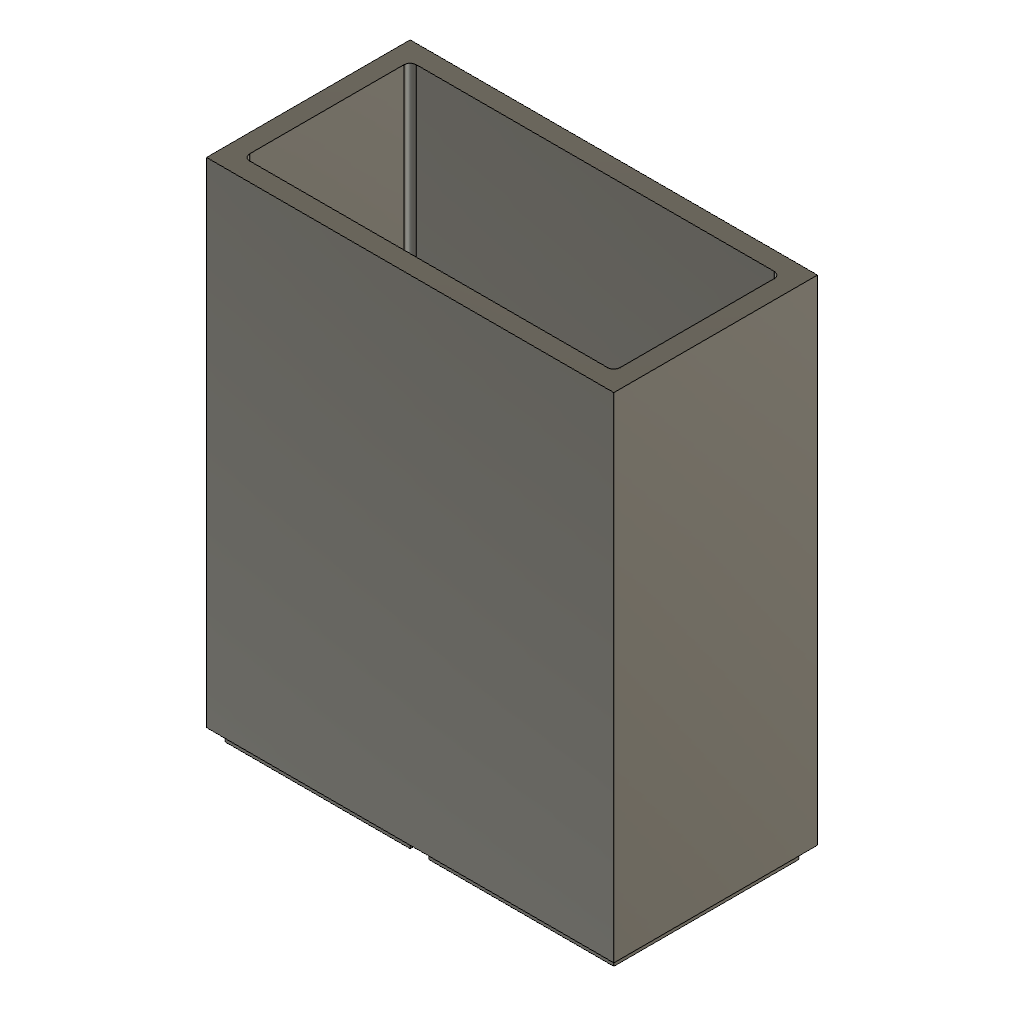
Double Compartment (Autodesk Fusion 360 design; units mm, degrees)
part number: 2026-10-19-01-57-47-434
Autodesk Fusion 360 part; units mm, degrees
sketch "Sketch1" plane through (0, 0, 0) normal (0, 0, 1) x (1, 0, 0)
  line L0 (-11, 35) -> (55, 35)
  line L1 (55, 35) -> (55, 2)
  line L2 (55, 2) -> (-11, 2)
  line L3 (-11, 2) -> (-11, 35)
  line L4 (-8, 32) -> (52, 32)
  line L5 (52, 32) -> (52, 5)
  line L6 (52, 5) -> (-8, 5)
  line L7 (-8, 5) -> (-8, 32)
  dimension "d1" = 33
  dimension "d2" = 66
  dimension "d3" = 3
  dimension "d4" = 3
  dimension "d5" = 3
  dimension "d6" = 3
  constraint horizontal L0
  constraint vertical L1
  constraint horizontal L2
  constraint vertical L3
  constraint horizontal L4
  constraint vertical L5
  constraint horizontal L6
  constraint vertical L7
  measures "d1" distance of L0 L2
  measures "d2" distance of L1 L3
  measures "d3" distance of L0 L4
  measures "d4" distance of L3 L7
  measures "d5" distance of L1 L5
  measures "d6" distance of L2 L6
extrude "Extrude1" add sketch "Sketch1" along normal blind 80
sketch "Sketch2" plane through (0, 0, 0) normal (0, 0, 1) x (1, 0, 0)
  line L0 (-11, 2) -> (55, 2)
  line L1 (55, 2) -> (55, 35)
  line L2 (55, 35) -> (-11, 35)
  line L3 (-11, 35) -> (-11, 2)
  constraint horizontal L0
  constraint vertical L1
  constraint horizontal L2
  constraint vertical L3
extrude "Extrude2" add sketch "Sketch2" along normal blind 3
sketch "Sketch3" plane through (0, 0, 0) normal (0, 0, 1) x (1, 0, 0)
  line L0 (-11, 2) -> (55, 2)
  line L1 (55, 2) -> (55, 35)
  line L2 (55, 35) -> (-11, 35)
  line L3 (-11, 35) -> (-11, 2)
  line L4 (-9.5, 3.5) -> (20.5, 3.5)
  line L5 (20.5, 3.5) -> (20.5, 33.5)
  line L6 (20.5, 33.5) -> (-9.5, 33.5)
  line L7 (-9.5, 33.5) -> (-9.5, 3.5)
  line L8 (23.5, 3.5) -> (53.5, 3.5)
  line L9 (53.5, 3.5) -> (53.5, 33.5)
  line L10 (53.5, 33.5) -> (23.5, 33.5)
  line L11 (23.5, 33.5) -> (23.5, 3.5)
  dimension "d11" = 66
  dimension "d12" = 33
  dimension "d13" = 1.5
  dimension "d14" = 1.5
  dimension "d15" = 3
  dimension "d16" = 30
  dimension "d18" = 30
  dimension "d19" = 30
  dimension "d20" = 1.5
  dimension "d21" = 1.5
  constraint horizontal L0
  constraint vertical L1
  constraint horizontal L2
  constraint vertical L3
  constraint horizontal L4
  constraint vertical L5
  constraint horizontal L6
  constraint vertical L7
  constraint horizontal L8
  constraint vertical L9
  constraint horizontal L10
  constraint vertical L11
  measures "d11" distance of L1 L3
  measures "d12" distance of L0 L2
  measures "d13" distance of L3 L7
  measures "d14" distance of L1 L9
  measures "d15" distance of L5 L11
  measures "d16" distance of L5 L7
  measures "d18" distance of L4 L6
  measures "d19" distance of L8 L10
  measures "d20" distance of L2 L6
  measures "d21" distance of L2 L10
extrude "Extrude3" add sketch "Sketch3" against normal blind 3 contours L4 L5 L6 L7 | L8 L9 L10 L11
chamfer "Chamfer1" distance 1 angle 45 2 faces at (0.5, 23.5, -3) (43.5, 13.5, -3) tangent chain off
fillet "Fillet1" radius 1 1 edges at (-8, 32, 41.5)
fillet "Fillet2" radius 1 1 edges at (52, 32, 41.5)
fillet "Fillet3" radius 1 1 edges at (52, 5, 41.5)
fillet "Fillet4" radius 1 1 edges at (-8, 5, 41.5)
